Autodesk Fusion 360 part; units mm, degrees
(part 2 of 2)
component "D_tp4056" placed x (1, 0, 0) y (0, 1, 0) z (0, 0, 1) at (0, 0, 0)
component "D_boost" placed x (1, 0, 0) y (0, 1, 0) z (0, 0, 1) at (0, 0, 0)
component "D_tag" placed x (1, 0, 0) y (0, 1, 0) z (0, 0, 1) at (0, 0, 0)
component "D_btn_poke (mode)" placed x (1, 0, 0) y (0, 1, 0) z (0, 0, 1) at (0, 0, 5)
component "D_btn (mode)" placed x (1, 0, 0) y (0, 1, 0) z (0, 0, 1) at (0, 0, 5)
component "D_oled_screen" placed x (1, 0, 0) y (0, 1, 0) z (0, 0, 1) at (0, 0, 0)
component "COVER" placed x (1, 0, 0) y (0, 1, 0) z (0, 0, 1) at (0, 0, 0)
component "SHELL" placed x (1, 0, 0) y (0, 1, 0) z (0, 0, 1) at (0, 0, 0)
equation "wall = 2.4 mm"
equation "floor_t = 2.4 mm"
equation "clear = 0.3 mm"
equation "hole_extra = 0.5 mm"
equation "insert_hole = 3.0 mm"
equation "m3_clear = 3.4 mm"
equation "fillet_r = 3.0 mm"
equation "corner_r = 6 mm"
equation "top_edge_r = 2 mm"
equation "esp_l = 55 mm"
equation "esp_w = 28 mm"
equation "esp_h = 13 mm"
equation "esp_usb_w = 9 mm"
equation "esp_usb_h = 3.5 mm"
equation "usb_plug_w = 13 mm"
equation "usb_plug_h = 7 mm"
equation "imu_l = 21 mm"
equation "imu_w = 16 mm"
equation "imu_h = 3 mm"
equation "oled_l = 28 mm"
equation "oled_w = 28 mm"
equation "oled_h = 5 mm"
equation "oled_win_l = 22 mm"
equation "oled_win_w = 11 mm"
equation "oled_win_top = 3 mm"
equation "btn_l = 6 mm"
equation "btn_w = 6 mm"
equation "btn_h = 5 mm"
equation "btn_act_d = 3.5 mm"
equation "btn_act_poke = 1.5 mm"
equation "sw_l = 8 mm"
equation "sw_w = 4 mm"
equation "sw_h = 4 mm"
equation "sw_lever_w = 1.5 mm"
equation "sw_lever_h = 3 mm"
equation "sw_travel = 2 mm"
equation "rgb_d = 5 mm"
equation "rgb_len = 8.6 mm"
equation "vib_d = 10 mm"
equation "vib_h = 3 mm"
equation "lipo_l = 52 mm"
equation "lipo_w = 35 mm"
equation "lipo_h = 8 mm"
equation "tp_l = 26 mm"
equation "tp_w = 17 mm"
equation "tp_h = 4 mm"
equation "tp_usb_w = 9 mm"
equation "tp_usb_h = 3.3 mm"
equation "boost_l = 40 mm"
equation "boost_w = 20 mm"
equation "boost_h = 12 mm"
equation "tag_l = 64 mm"
equation "tag_w = 36 mm"
equation "tag_h = 10 mm"
equation "body_l = 142 mm"
equation "body_w = 76 mm"
equation "body_h = 36 mm"
equation "shell_h = 20 mm"
equation "cover_h = body_h - shell_h"
equation "inner_l = body_l - 2 * wall"
equation "inner_w = body_w - 2 * wall"
equation "lip_t = 1.2 mm"
equation "lip_h = 3 mm"
equation "rim_t = 1.6 mm"
equation "arm_t = 1.6 mm"
equation "cup_in = 9.4 mm"
equation "cup_out = cup_in + 2 * arm_t"
equation "post_d = 5 mm"
equation "post_h = shell_h - wall"
equation "post_depth = 5 mm"
equation "post_x_r = -8 mm"
equation "post_x_f = 63 mm"
equation "post_y = 31 mm"
equation "screw_hole = 2.6 mm"
equation "screw_head_d = 4.6 mm"
equation "screw_head_h = 1.6 mm"
equation "cap_d = 6 mm"
equation "cap_hole = cap_d + 0.4 mm"
equation "cap_flange_d = 8 mm"
equation "cap_flange_t = 1.2 mm"
equation "cap_proud = 0.8 mm"
equation "esp_cx = -40.5 mm"
equation "esp_cy = 17 mm"
equation "oled_cx = -40.5 mm"
equation "oled_cy = -17 mm"
equation "btn_x = -6 mm"
equation "btn_y = 12 mm"
equation "rgb_x = -6 mm"
equation "rgb_y = 0 mm"
equation "tag_cx = 35 mm"
equation "tag_cy = -8 mm"
equation "imu_cx = 30 mm"
equation "imu_cy = 24 mm"
equation "lipo_cx = -34 mm"
equation "lipo_cy = 0 mm"
equation "boost_cx = 20 mm"
equation "boost_cy = -18 mm"
equation "tp_cx = 17 mm"
equation "tp_cy = 22 mm"
equation "vib_cx = 55 mm"
equation "vib_cy = 0 mm"
equation "sw_cx = 20 mm"
equation "z_oled = body_h - wall - oled_h"
equation "z_esp = body_h - wall - 1 mm - esp_h"
equation "z_tag = body_h - wall - 1 mm - tag_h"
equation "z_imu = body_h - wall - 1 mm - imu_h"
equation "z_btn = body_h - wall - cap_flange_t - 0.3 mm - btn_act_poke - btn_h"
equation "z_rgb = body_h - 0.3 mm - rgb_len"
equation "z_floor_parts = floor_t"
equation "esp_usb_z = z_esp + esp_h - esp_usb_h / 2 - 2 mm"
equation "tp_usb_z = floor_t + 1 mm + tp_h / 2"
equation "sw_cy = -( inner_w / 2 - clear - sw_w / 2 )"
equation "sw_z = floor_t + 1 mm + sw_h / 2"
equation "d114 = esp_l"
equation "d115 = esp_w"
equation "d116 = esp_h"
equation "d118 = esp_usb_w"
equation "d119 = esp_usb_h"
equation "d122 = imu_l"
equation "d123 = imu_w"
equation "d124 = imu_h"
equation "d126 = oled_l"
equation "d127 = oled_w"
equation "d128 = oled_h"
equation "d130 = oled_win_l"
equation "d131 = oled_win_w"
equation "d134 = btn_l"
equation "d135 = btn_w"
equation "d136 = btn_h"
equation "d138 = btn_act_d"
equation "d139 = btn_act_poke"
equation "d141 = sw_l"
equation "d142 = sw_w"
equation "d143 = sw_h"
equation "d145 = sw_lever_w"
equation "d146 = sw_lever_w"
equation "d147 = sw_lever_h"
equation "d149 = rgb_d"
equation "d150 = rgb_len"
equation "d152 = vib_d"
equation "d153 = vib_h"
equation "d155 = lipo_l"
equation "d156 = lipo_w"
equation "d157 = lip_h"
equation "d159 = tp_l"
equation "d160 = tp_w"
equation "d161 = tp_h"
equation "d163 = boost_l"
equation "d164 = boost_w"
equation "d165 = boost_h"
equation "d167 = tag_l"
equation "d168 = tag_w"
equation "d169 = tag_h"
equation "d175 = oled_win_l"
equation "d176 = oled_win_w"
equation "d179 = oled_win_w"
equation "d180 = oled_win_l"
equation "d183 = body_l"
equation "d184 = body_w"
equation "d185 = corner_r"
equation "d186 = body_h"
equation "d189 = top_edge_r"
equation "d190 = cover_h"
equation "d192 = wall"
equation "d193 = clear"
equation "d194 = rim_t"
equation "d195 = -oled_h"
equation "d197 = clear"
equation "d198 = rim_t"
equation "d199 = esp_h / 2"
equation "d201 = clear"
equation "d202 = rim_t"
equation "d203 = imu_h + 1 mm"
equation "d205 = -clear"
equation "d206 = -rim_t"
equation "d207 = tag_h / 2"
equation "d209 = clear"
equation "d210 = rim_t"
equation "d211 = rgb_len / 2"
equation "d225 = -imu_h - 1 mm"
equation "d229 = -esp_h / 2"
equation "d233 = -tag_h / 2"
equation "d235 = cup_in"
equation "d236 = cup_in + 1.5 mm"
equation "d237 = cup_in"
equation "d238 = cup_in + 1.5 mm"
equation "d239 = cap_flange_t + 0.3 mm + btn_act_poke + btn_h"
equation "d241 = post_d"
equation "d242 = post_d"
equation "d243 = post_d"
equation "d244 = post_d"
equation "d245 = post_h"
equation "d247 = insert_hole"
equation "d248 = insert_hole"
equation "d249 = insert_hole"
equation "d250 = insert_hole"
equation "d251 = -post_depth"
equation "d261 = wall"
equation "d262 = post_d"
equation "d263 = post_d"
equation "d264 = post_d"
equation "d265 = post_d"
equation "d268 = screw_hole"
equation "d269 = screw_hole"
equation "d270 = screw_hole"
equation "d271 = screw_hole"
equation "d274 = screw_head_d"
equation "d275 = screw_head_d"
equation "d276 = screw_head_d"
equation "d277 = screw_head_d"
equation "d278 = -screw_head_h"
equation "d280 = clear"
equation "d281 = rim_t"
equation "d282 = lip_h / 2"
equation "d288 = clear"
equation "d289 = rim_t"
equation "d290 = boost_h / 2"
equation "d292 = clear"
equation "d293 = rim_t"
equation "d294 = vib_h"
equation "d296 = clear"
equation "d297 = rim_t"
equation "d298 = tp_h + 1 mm"
equation "d300 = usb_plug_w"
equation "d301 = usb_plug_h"
named bodies: "D_esp32", "D_imu", "D_oled_board", "D_btn(arm)", "D_btn_poke(arm)", "D_switch_body", "D_switch_lever", "D_rgb", "D_vib", "D_lipo", "D_tp4056", "D_boost", "D_tag", "D_btn_poke", "D_btn", "D_btn_poke (mode)", "D_btn (mode)", "D_oled_screen", "cover_body", "shell_body"
